Autodesk Fusion 360 part; units mm, degrees
(part 2 of 2)
  constraint tangent L75 A74
  constraint tangent L75 A75
  constraint tangent L72 A75
  constraint tangent L76 A76
  constraint tangent L77 A76
  constraint tangent L77 A77
  constraint tangent L78 A77
  constraint tangent L78 A78
  constraint tangent L79 A78
  constraint tangent L79 A79
  constraint tangent L76 A79
  constraint tangent L80 A80
  constraint tangent L81 A80
  constraint tangent L81 A81
  constraint tangent L82 A81
  constraint tangent L82 A82
  constraint tangent L83 A82
  constraint tangent L83 A83
  constraint tangent L80 A83
  constraint tangent L84 A84
  constraint tangent L85 A84
  constraint tangent L85 A85
  constraint tangent L86 A85
  constraint tangent L86 A86
  constraint tangent L87 A86
  constraint tangent L87 A87
  constraint tangent L84 A87
  constraint tangent L88 A88
  constraint tangent L89 A88
  constraint tangent L89 A89
  constraint tangent L90 A89
  constraint tangent L90 A90
  constraint tangent L91 A90
  constraint tangent L91 A91
  constraint tangent L88 A91
  constraint tangent L92 A92
  constraint tangent L93 A92
  constraint tangent L93 A93
  constraint tangent L94 A93
  constraint tangent L94 A94
  constraint tangent L95 A94
  constraint tangent L95 A95
  constraint tangent L92 A95
  constraint tangent L96 A96
  constraint tangent L97 A96
  constraint tangent L97 A97
  constraint tangent L98 A97
  constraint tangent L98 A98
  constraint tangent L99 A98
  constraint tangent L99 A99
  constraint tangent L96 A99
  constraint tangent L100 A100
  constraint tangent L101 A100
  constraint tangent L101 A101
  constraint tangent L102 A101
  constraint tangent L102 A102
  constraint tangent L103 A102
  constraint tangent L103 A103
  constraint tangent L100 A103
  constraint tangent L104 A104
  constraint tangent L105 A104
  constraint tangent L105 A105
  constraint tangent L106 A105
  constraint tangent L106 A106
  constraint tangent L107 A106
  constraint tangent L107 A107
  constraint tangent L104 A107
  constraint tangent L108 A108
  constraint tangent L109 A108
  constraint tangent L109 A109
  constraint tangent L110 A109
  constraint tangent L110 A110
  constraint tangent L111 A110
  constraint tangent L111 A111
  constraint tangent L108 A111
  constraint tangent L112 A112
  constraint tangent L113 A112
  constraint tangent L113 A113
  constraint tangent L114 A113
  constraint tangent L114 A114
  constraint tangent L115 A114
  constraint tangent L115 A115
  constraint tangent L112 A115
  constraint tangent L116 A116
  constraint tangent L117 A116
  constraint tangent L117 A117
  constraint tangent L118 A117
  constraint tangent L118 A118
  constraint tangent L119 A118
  constraint tangent L119 A119
  constraint tangent L116 A119
  constraint tangent L120 A120
  constraint tangent L121 A120
  constraint tangent L121 A121
  constraint tangent L122 A121
  constraint tangent L122 A122
  constraint tangent L123 A122
  constraint tangent L123 A123
  constraint tangent L120 A123
  constraint tangent L124 A124
  constraint tangent L125 A124
  constraint tangent L125 A125
  constraint tangent L126 A125
  constraint tangent L126 A126
  constraint tangent L127 A126
  constraint tangent L127 A127
  constraint tangent L124 A127
  constraint tangent L128 A128
  constraint tangent L129 A128
  constraint tangent L129 A129
  constraint tangent L130 A129
  constraint tangent L130 A130
  constraint tangent L131 A130
  constraint tangent L131 A131
  constraint tangent L128 A131
  constraint tangent L132 A132
  constraint tangent L133 A132
  constraint tangent L133 A133
  constraint tangent L134 A133
  constraint tangent L134 A134
  constraint tangent L135 A134
  constraint tangent L135 A135
  constraint tangent L132 A135
  constraint tangent L136 A136
  constraint tangent L137 A136
  constraint tangent L137 A137
  constraint tangent L138 A137
  constraint tangent L138 A138
  constraint tangent L139 A138
  constraint tangent L139 A139
  constraint tangent L136 A139
  constraint tangent L140 A140
  constraint tangent L141 A140
  constraint tangent L141 A141
  constraint tangent L142 A141
  constraint tangent L142 A142
  constraint tangent L143 A142
  constraint tangent L143 A143
  constraint tangent L140 A143
extrude "Right recessed grille" cut sketch "Esboço41" along normal blind 1.55 bodies 1
ref_plane "Plano de trabalho26" through (-27, 0, 0) normal (1, 0, 0) x (0, 1, 0)
sketch "Esboço42" plane through (-27, 0, 0) normal (1, 0, 0) x (0, 0, -1)
  line L0 (49.75, 12) -> (52.25, 12)
  line L1 (52.5, 12.25) -> (52.5, 12.55)
  line L2 (52.25, 12.8) -> (49.75, 12.8)
  line L3 (49.5, 12.55) -> (49.5, 12.25)
  arc A0 (52.25, 12) -> (52.5, 12.25) centre (52.25, 12.25) ccw
  arc A1 (52.5, 12.55) -> (52.25, 12.8) centre (52.25, 12.55) ccw
  arc A2 (49.75, 12.8) -> (49.5, 12.55) centre (49.75, 12.55) ccw
  arc A3 (49.5, 12.25) -> (49.75, 12) centre (49.75, 12.25) ccw
  line L4 (45.35, 12) -> (47.85, 12)
  line L5 (48.1, 12.25) -> (48.1, 12.55)
  line L6 (47.85, 12.8) -> (45.35, 12.8)
  line L7 (45.1, 12.55) -> (45.1, 12.25)
  arc A4 (47.85, 12) -> (48.1, 12.25) centre (47.85, 12.25) ccw
  arc A5 (48.1, 12.55) -> (47.85, 12.8) centre (47.85, 12.55) ccw
  arc A6 (45.35, 12.8) -> (45.1, 12.55) centre (45.35, 12.55) ccw
  arc A7 (45.1, 12.25) -> (45.35, 12) centre (45.35, 12.25) ccw
  line L8 (40.95, 12) -> (43.45, 12)
  line L9 (43.7, 12.25) -> (43.7, 12.55)
  line L10 (43.45, 12.8) -> (40.95, 12.8)
  line L11 (40.7, 12.55) -> (40.7, 12.25)
  arc A8 (43.45, 12) -> (43.7, 12.25) centre (43.45, 12.25) ccw
  arc A9 (43.7, 12.55) -> (43.45, 12.8) centre (43.45, 12.55) ccw
  arc A10 (40.95, 12.8) -> (40.7, 12.55) centre (40.95, 12.55) ccw
  arc A11 (40.7, 12.25) -> (40.95, 12) centre (40.95, 12.25) ccw
  line L12 (36.55, 12) -> (39.05, 12)
  line L13 (39.3, 12.25) -> (39.3, 12.55)
  line L14 (39.05, 12.8) -> (36.55, 12.8)
  line L15 (36.3, 12.55) -> (36.3, 12.25)
  arc A12 (39.05, 12) -> (39.3, 12.25) centre (39.05, 12.25) ccw
  arc A13 (39.3, 12.55) -> (39.05, 12.8) centre (39.05, 12.55) ccw
  arc A14 (36.55, 12.8) -> (36.3, 12.55) centre (36.55, 12.55) ccw
  arc A15 (36.3, 12.25) -> (36.55, 12) centre (36.55, 12.25) ccw
  line L16 (32.15, 12) -> (34.65, 12)
  line L17 (34.9, 12.25) -> (34.9, 12.55)
  line L18 (34.65, 12.8) -> (32.15, 12.8)
  line L19 (31.9, 12.55) -> (31.9, 12.25)
  arc A16 (34.65, 12) -> (34.9, 12.25) centre (34.65, 12.25) ccw
  arc A17 (34.9, 12.55) -> (34.65, 12.8) centre (34.65, 12.55) ccw
  arc A18 (32.15, 12.8) -> (31.9, 12.55) centre (32.15, 12.55) ccw
  arc A19 (31.9, 12.25) -> (32.15, 12) centre (32.15, 12.25) ccw
  line L20 (27.75, 12) -> (30.25, 12)
  line L21 (30.5, 12.25) -> (30.5, 12.55)
  line L22 (30.25, 12.8) -> (27.75, 12.8)
  line L23 (27.5, 12.55) -> (27.5, 12.25)
  arc A20 (30.25, 12) -> (30.5, 12.25) centre (30.25, 12.25) ccw
  arc A21 (30.5, 12.55) -> (30.25, 12.8) centre (30.25, 12.55) ccw
  arc A22 (27.75, 12.8) -> (27.5, 12.55) centre (27.75, 12.55) ccw
  arc A23 (27.5, 12.25) -> (27.75, 12) centre (27.75, 12.25) ccw
  line L24 (23.35, 12) -> (25.85, 12)
  line L25 (26.1, 12.25) -> (26.1, 12.55)
  line L26 (25.85, 12.8) -> (23.35, 12.8)
  line L27 (23.1, 12.55) -> (23.1, 12.25)
  arc A24 (25.85, 12) -> (26.1, 12.25) centre (25.85, 12.25) ccw
  arc A25 (26.1, 12.55) -> (25.85, 12.8) centre (25.85, 12.55) ccw
  arc A26 (23.35, 12.8) -> (23.1, 12.55) centre (23.35, 12.55) ccw
  arc A27 (23.1, 12.25) -> (23.35, 12) centre (23.35, 12.25) ccw
  line L28 (18.95, 12) -> (21.45, 12)
  line L29 (21.7, 12.25) -> (21.7, 12.55)
  line L30 (21.45, 12.8) -> (18.95, 12.8)
  line L31 (18.7, 12.55) -> (18.7, 12.25)
  arc A28 (21.45, 12) -> (21.7, 12.25) centre (21.45, 12.25) ccw
  arc A29 (21.7, 12.55) -> (21.45, 12.8) centre (21.45, 12.55) ccw
  arc A30 (18.95, 12.8) -> (18.7, 12.55) centre (18.95, 12.55) ccw
  arc A31 (18.7, 12.25) -> (18.95, 12) centre (18.95, 12.25) ccw
  line L32 (14.55, 12) -> (17.05, 12)
  line L33 (17.3, 12.25) -> (17.3, 12.55)
  line L34 (17.05, 12.8) -> (14.55, 12.8)
  line L35 (14.3, 12.55) -> (14.3, 12.25)
  arc A32 (17.05, 12) -> (17.3, 12.25) centre (17.05, 12.25) ccw
  arc A33 (17.3, 12.55) -> (17.05, 12.8) centre (17.05, 12.55) ccw
  arc A34 (14.55, 12.8) -> (14.3, 12.55) centre (14.55, 12.55) ccw
  arc A35 (14.3, 12.25) -> (14.55, 12) centre (14.55, 12.25) ccw
  line L36 (49.75, 13.8) -> (52.25, 13.8)
  line L37 (52.5, 14.05) -> (52.5, 14.35)
  line L38 (52.25, 14.6) -> (49.75, 14.6)
  line L39 (49.5, 14.35) -> (49.5, 14.05)
  arc A36 (52.25, 13.8) -> (52.5, 14.05) centre (52.25, 14.05) ccw
  arc A37 (52.5, 14.35) -> (52.25, 14.6) centre (52.25, 14.35) ccw
  arc A38 (49.75, 14.6) -> (49.5, 14.35) centre (49.75, 14.35) ccw
  arc A39 (49.5, 14.05) -> (49.75, 13.8) centre (49.75, 14.05) ccw
  line L40 (45.35, 13.8) -> (47.85, 13.8)
  line L41 (48.1, 14.05) -> (48.1, 14.35)
  line L42 (47.85, 14.6) -> (45.35, 14.6)
  line L43 (45.1, 14.35) -> (45.1, 14.05)
  arc A40 (47.85, 13.8) -> (48.1, 14.05) centre (47.85, 14.05) ccw
  arc A41 (48.1, 14.35) -> (47.85, 14.6) centre (47.85, 14.35) ccw
  arc A42 (45.35, 14.6) -> (45.1, 14.35) centre (45.35, 14.35) ccw
  arc A43 (45.1, 14.05) -> (45.35, 13.8) centre (45.35, 14.05) ccw
  line L44 (40.95, 13.8) -> (43.45, 13.8)
  line L45 (43.7, 14.05) -> (43.7, 14.35)
  line L46 (43.45, 14.6) -> (40.95, 14.6)
  line L47 (40.7, 14.35) -> (40.7, 14.05)
  arc A44 (43.45, 13.8) -> (43.7, 14.05) centre (43.45, 14.05) ccw
  arc A45 (43.7, 14.35) -> (43.45, 14.6) centre (43.45, 14.35) ccw
  arc A46 (40.95, 14.6) -> (40.7, 14.35) centre (40.95, 14.35) ccw
  arc A47 (40.7, 14.05) -> (40.95, 13.8) centre (40.95, 14.05) ccw
  line L48 (36.55, 13.8) -> (39.05, 13.8)
  line L49 (39.3, 14.05) -> (39.3, 14.35)
  line L50 (39.05, 14.6) -> (36.55, 14.6)
  line L51 (36.3, 14.35) -> (36.3, 14.05)
  arc A48 (39.05, 13.8) -> (39.3, 14.05) centre (39.05, 14.05) ccw
  arc A49 (39.3, 14.35) -> (39.05, 14.6) centre (39.05, 14.35) ccw
  arc A50 (36.55, 14.6) -> (36.3, 14.35) centre (36.55, 14.35) ccw
  arc A51 (36.3, 14.05) -> (36.55, 13.8) centre (36.55, 14.05) ccw
  line L52 (32.15, 13.8) -> (34.65, 13.8)
  line L53 (34.9, 14.05) -> (34.9, 14.35)
  line L54 (34.65, 14.6) -> (32.15, 14.6)
  line L55 (31.9, 14.35) -> (31.9, 14.05)
  arc A52 (34.65, 13.8) -> (34.9, 14.05) centre (34.65, 14.05) ccw
  arc A53 (34.9, 14.35) -> (34.65, 14.6) centre (34.65, 14.35) ccw
  arc A54 (32.15, 14.6) -> (31.9, 14.35) centre (32.15, 14.35) ccw
  arc A55 (31.9, 14.05) -> (32.15, 13.8) centre (32.15, 14.05) ccw
  line L56 (27.75, 13.8) -> (30.25, 13.8)
  line L57 (30.5, 14.05) -> (30.5, 14.35)
  line L58 (30.25, 14.6) -> (27.75, 14.6)
  line L59 (27.5, 14.35) -> (27.5, 14.05)
  arc A56 (30.25, 13.8) -> (30.5, 14.05) centre (30.25, 14.05) ccw
  arc A57 (30.5, 14.35) -> (30.25, 14.6) centre (30.25, 14.35) ccw
  arc A58 (27.75, 14.6) -> (27.5, 14.35) centre (27.75, 14.35) ccw
  arc A59 (27.5, 14.05) -> (27.75, 13.8) centre (27.75, 14.05) ccw
  line L60 (23.35, 13.8) -> (25.85, 13.8)
  line L61 (26.1, 14.05) -> (26.1, 14.35)
  line L62 (25.85, 14.6) -> (23.35, 14.6)
  line L63 (23.1, 14.35) -> (23.1, 14.05)
  arc A60 (25.85, 13.8) -> (26.1, 14.05) centre (25.85, 14.05) ccw
  arc A61 (26.1, 14.35) -> (25.85, 14.6) centre (25.85, 14.35) ccw
  arc A62 (23.35, 14.6) -> (23.1, 14.35) centre (23.35, 14.35) ccw
  arc A63 (23.1, 14.05) -> (23.35, 13.8) centre (23.35, 14.05) ccw
  line L64 (18.95, 13.8) -> (21.45, 13.8)
  line L65 (21.7, 14.05) -> (21.7, 14.35)
  line L66 (21.45, 14.6) -> (18.95, 14.6)
  line L67 (18.7, 14.35) -> (18.7, 14.05)
  arc A64 (21.45, 13.8) -> (21.7, 14.05) centre (21.45, 14.05) ccw
  arc A65 (21.7, 14.35) -> (21.45, 14.6) centre (21.45, 14.35) ccw
  arc A66 (18.95, 14.6) -> (18.7, 14.35) centre (18.95, 14.35) ccw
  arc A67 (18.7, 14.05) -> (18.95, 13.8) centre (18.95, 14.05) ccw
  line L68 (14.55, 13.8) -> (17.05, 13.8)
  line L69 (17.3, 14.05) -> (17.3, 14.35)
  line L70 (17.05, 14.6) -> (14.55, 14.6)
  line L71 (14.3, 14.35) -> (14.3, 14.05)
  arc A68 (17.05, 13.8) -> (17.3, 14.05) centre (17.05, 14.05) ccw
  arc A69 (17.3, 14.35) -> (17.05, 14.6) centre (17.05, 14.35) ccw
  arc A70 (14.55, 14.6) -> (14.3, 14.35) centre (14.55, 14.35) ccw
  arc A71 (14.3, 14.05) -> (14.55, 13.8) centre (14.55, 14.05) ccw
  line L72 (49.75, 15.6) -> (52.25, 15.6)
  line L73 (52.5, 15.85) -> (52.5, 16.15)
  line L74 (52.25, 16.4) -> (49.75, 16.4)
  line L75 (49.5, 16.15) -> (49.5, 15.85)
  arc A72 (52.25, 15.6) -> (52.5, 15.85) centre (52.25, 15.85) ccw
  arc A73 (52.5, 16.15) -> (52.25, 16.4) centre (52.25, 16.15) ccw
  arc A74 (49.75, 16.4) -> (49.5, 16.15) centre (49.75, 16.15) ccw
  arc A75 (49.5, 15.85) -> (49.75, 15.6) centre (49.75, 15.85) ccw
  line L76 (45.35, 15.6) -> (47.85, 15.6)
  line L77 (48.1, 15.85) -> (48.1, 16.15)
  line L78 (47.85, 16.4) -> (45.35, 16.4)
  line L79 (45.1, 16.15) -> (45.1, 15.85)
  arc A76 (47.85, 15.6) -> (48.1, 15.85) centre (47.85, 15.85) ccw
  arc A77 (48.1, 16.15) -> (47.85, 16.4) centre (47.85, 16.15) ccw
  arc A78 (45.35, 16.4) -> (45.1, 16.15) centre (45.35, 16.15) ccw
  arc A79 (45.1, 15.85) -> (45.35, 15.6) centre (45.35, 15.85) ccw
  line L80 (40.95, 15.6) -> (43.45, 15.6)
  line L81 (43.7, 15.85) -> (43.7, 16.15)
  line L82 (43.45, 16.4) -> (40.95, 16.4)
  line L83 (40.7, 16.15) -> (40.7, 15.85)
  arc A80 (43.45, 15.6) -> (43.7, 15.85) centre (43.45, 15.85) ccw
  arc A81 (43.7, 16.15) -> (43.45, 16.4) centre (43.45, 16.15) ccw
  arc A82 (40.95, 16.4) -> (40.7, 16.15) centre (40.95, 16.15) ccw
  arc A83 (40.7, 15.85) -> (40.95, 15.6) centre (40.95, 15.85) ccw
  line L84 (36.55, 15.6) -> (39.05, 15.6)
  line L85 (39.3, 15.85) -> (39.3, 16.15)
  line L86 (39.05, 16.4) -> (36.55, 16.4)
  line L87 (36.3, 16.15) -> (36.3, 15.85)
  arc A84 (39.05, 15.6) -> (39.3, 15.85) centre (39.05, 15.85) ccw
  arc A85 (39.3, 16.15) -> (39.05, 16.4) centre (39.05, 16.15) ccw
  arc A86 (36.55, 16.4) -> (36.3, 16.15) centre (36.55, 16.15) ccw
  arc A87 (36.3, 15.85) -> (36.55, 15.6) centre (36.55, 15.85) ccw
  line L88 (32.15, 15.6) -> (34.65, 15.6)
  line L89 (34.9, 15.85) -> (34.9, 16.15)
  line L90 (34.65, 16.4) -> (32.15, 16.4)
  line L91 (31.9, 16.15) -> (31.9, 15.85)
  arc A88 (34.65, 15.6) -> (34.9, 15.85) centre (34.65, 15.85) ccw
  arc A89 (34.9, 16.15) -> (34.65, 16.4) centre (34.65, 16.15) ccw
  arc A90 (32.15, 16.4) -> (31.9, 16.15) centre (32.15, 16.15) ccw
  arc A91 (31.9, 15.85) -> (32.15, 15.6) centre (32.15, 15.85) ccw
  line L92 (27.75, 15.6) -> (30.25, 15.6)
  line L93 (30.5, 15.85) -> (30.5, 16.15)
  line L94 (30.25, 16.4) -> (27.75, 16.4)
  line L95 (27.5, 16.15) -> (27.5, 15.85)
  arc A92 (30.25, 15.6) -> (30.5, 15.85) centre (30.25, 15.85) ccw
  arc A93 (30.5, 16.15) -> (30.25, 16.4) centre (30.25, 16.15) ccw
  arc A94 (27.75, 16.4) -> (27.5, 16.15) centre (27.75, 16.15) ccw
  arc A95 (27.5, 15.85) -> (27.75, 15.6) centre (27.75, 15.85) ccw
  line L96 (23.35, 15.6) -> (25.85, 15.6)
  line L97 (26.1, 15.85) -> (26.1, 16.15)
  line L98 (25.85, 16.4) -> (23.35, 16.4)
  line L99 (23.1, 16.15) -> (23.1, 15.85)
  arc A96 (25.85, 15.6) -> (26.1, 15.85) centre (25.85, 15.85) ccw
  arc A97 (26.1, 16.15) -> (25.85, 16.4) centre (25.85, 16.15) ccw
  arc A98 (23.35, 16.4) -> (23.1, 16.15) centre (23.35, 16.15) ccw
  arc A99 (23.1, 15.85) -> (23.35, 15.6) centre (23.35, 15.85) ccw
  line L100 (18.95, 15.6) -> (21.45, 15.6)
  line L101 (21.7, 15.85) -> (21.7, 16.15)
  line L102 (21.45, 16.4) -> (18.95, 16.4)
  line L103 (18.7, 16.15) -> (18.7, 15.85)
  arc A100 (21.45, 15.6) -> (21.7, 15.85) centre (21.45, 15.85) ccw
  arc A101 (21.7, 16.15) -> (21.45, 16.4) centre (21.45, 16.15) ccw
  arc A102 (18.95, 16.4) -> (18.7, 16.15) centre (18.95, 16.15) ccw
  arc A103 (18.7, 15.85) -> (18.95, 15.6) centre (18.95, 15.85) ccw
  line L104 (14.55, 15.6) -> (17.05, 15.6)
  line L105 (17.3, 15.85) -> (17.3, 16.15)
  line L106 (17.05, 16.4) -> (14.55, 16.4)
  line L107 (14.3, 16.15) -> (14.3, 15.85)
  arc A104 (17.05, 15.6) -> (17.3, 15.85) centre (17.05, 15.85) ccw
  arc A105 (17.3, 16.15) -> (17.05, 16.4) centre (17.05, 16.15) ccw
  arc A106 (14.55, 16.4) -> (14.3, 16.15) centre (14.55, 16.15) ccw
  arc A107 (14.3, 15.85) -> (14.55, 15.6) centre (14.55, 15.85) ccw
  line L108 (49.75, 17.4) -> (52.25, 17.4)
  line L109 (52.5, 17.65) -> (52.5, 17.95)
  line L110 (52.25, 18.2) -> (49.75, 18.2)
  line L111 (49.5, 17.95) -> (49.5, 17.65)
  arc A108 (52.25, 17.4) -> (52.5, 17.65) centre (52.25, 17.65) ccw
  arc A109 (52.5, 17.95) -> (52.25, 18.2) centre (52.25, 17.95) ccw
  arc A110 (49.75, 18.2) -> (49.5, 17.95) centre (49.75, 17.95) ccw
  arc A111 (49.5, 17.65) -> (49.75, 17.4) centre (49.75, 17.65) ccw
  line L112 (45.35, 17.4) -> (47.85, 17.4)
  line L113 (48.1, 17.65) -> (48.1, 17.95)
  line L114 (47.85, 18.2) -> (45.35, 18.2)
  line L115 (45.1, 17.95) -> (45.1, 17.65)
  arc A112 (47.85, 17.4) -> (48.1, 17.65) centre (47.85, 17.65) ccw
  arc A113 (48.1, 17.95) -> (47.85, 18.2) centre (47.85, 17.95) ccw
  arc A114 (45.35, 18.2) -> (45.1, 17.95) centre (45.35, 17.95) ccw
  arc A115 (45.1, 17.65) -> (45.35, 17.4) centre (45.35, 17.65) ccw
  line L116 (40.95, 17.4) -> (43.45, 17.4)
  line L117 (43.7, 17.65) -> (43.7, 17.95)
  line L118 (43.45, 18.2) -> (40.95, 18.2)
  line L119 (40.7, 17.95) -> (40.7, 17.65)
  arc A116 (43.45, 17.4) -> (43.7, 17.65) centre (43.45, 17.65) ccw
  arc A117 (43.7, 17.95) -> (43.45, 18.2) centre (43.45, 17.95) ccw
  arc A118 (40.95, 18.2) -> (40.7, 17.95) centre (40.95, 17.95) ccw
  arc A119 (40.7, 17.65) -> (40.95, 17.4) centre (40.95, 17.65) ccw
  line L120 (36.55, 17.4) -> (39.05, 17.4)
  line L121 (39.3, 17.65) -> (39.3, 17.95)
  line L122 (39.05, 18.2) -> (36.55, 18.2)
  line L123 (36.3, 17.95) -> (36.3, 17.65)
  arc A120 (39.05, 17.4) -> (39.3, 17.65) centre (39.05, 17.65) ccw
  arc A121 (39.3, 17.95) -> (39.05, 18.2) centre (39.05, 17.95) ccw
  arc A122 (36.55, 18.2) -> (36.3, 17.95) centre (36.55, 17.95) ccw
  arc A123 (36.3, 17.65) -> (36.55, 17.4) centre (36.55, 17.65) ccw
  line L124 (32.15, 17.4) -> (34.65, 17.4)
  line L125 (34.9, 17.65) -> (34.9, 17.95)
  line L126 (34.65, 18.2) -> (32.15, 18.2)
  line L127 (31.9, 17.95) -> (31.9, 17.65)
  arc A124 (34.65, 17.4) -> (34.9, 17.65) centre (34.65, 17.65) ccw
  arc A125 (34.9, 17.95) -> (34.65, 18.2) centre (34.65, 17.95) ccw
  arc A126 (32.15, 18.2) -> (31.9, 17.95) centre (32.15, 17.95) ccw
  arc A127 (31.9, 17.65) -> (32.15, 17.4) centre (32.15, 17.65) ccw
  line L128 (27.75, 17.4) -> (30.25, 17.4)
  line L129 (30.5, 17.65) -> (30.5, 17.95)
  line L130 (30.25, 18.2) -> (27.75, 18.2)
  line L131 (27.5, 17.95) -> (27.5, 17.65)
  arc A128 (30.25, 17.4) -> (30.5, 17.65) centre (30.25, 17.65) ccw
  arc A129 (30.5, 17.95) -> (30.25, 18.2) centre (30.25, 17.95) ccw
  arc A130 (27.75, 18.2) -> (27.5, 17.95) centre (27.75, 17.95) ccw
  arc A131 (27.5, 17.65) -> (27.75, 17.4) centre (27.75, 17.65) ccw
  line L132 (23.35, 17.4) -> (25.85, 17.4)
  line L133 (26.1, 17.65) -> (26.1, 17.95)
  line L134 (25.85, 18.2) -> (23.35, 18.2)
  line L135 (23.1, 17.95) -> (23.1, 17.65)
  arc A132 (25.85, 17.4) -> (26.1, 17.65) centre (25.85, 17.65) ccw
  arc A133 (26.1, 17.95) -> (25.85, 18.2) centre (25.85, 17.95) ccw
  arc A134 (23.35, 18.2) -> (23.1, 17.95) centre (23.35, 17.95) ccw
  arc A135 (23.1, 17.65) -> (23.35, 17.4) centre (23.35, 17.65) ccw
  line L136 (18.95, 17.4) -> (21.45, 17.4)
  line L137 (21.7, 17.65) -> (21.7, 17.95)
  line L138 (21.45, 18.2) -> (18.95, 18.2)
  line L139 (18.7, 17.95) -> (18.7, 17.65)
  arc A136 (21.45, 17.4) -> (21.7, 17.65) centre (21.45, 17.65) ccw
  arc A137 (21.7, 17.95) -> (21.45, 18.2) centre (21.45, 17.95) ccw
  arc A138 (18.95, 18.2) -> (18.7, 17.95) centre (18.95, 17.95) ccw
  arc A139 (18.7, 17.65) -> (18.95, 17.4) centre (18.95, 17.65) ccw
  line L140 (14.55, 17.4) -> (17.05, 17.4)
  line L141 (17.3, 17.65) -> (17.3, 17.95)
  line L142 (17.05, 18.2) -> (14.55, 18.2)
  line L143 (14.3, 17.95) -> (14.3, 17.65)
  arc A140 (17.05, 17.4) -> (17.3, 17.65) centre (17.05, 17.65) ccw
  arc A141 (17.3, 17.95) -> (17.05, 18.2) centre (17.05, 17.95) ccw
  arc A142 (14.55, 18.2) -> (14.3, 17.95) centre (14.55, 17.95) ccw
  arc A143 (14.3, 17.65) -> (14.55, 17.4) centre (14.55, 17.65) ccw
  constraint tangent L0 A0
  constraint tangent L1 A0
  constraint tangent L1 A1
  constraint tangent L2 A1
  constraint tangent L2 A2
  constraint tangent L3 A2
  constraint tangent L3 A3
  constraint tangent L0 A3
  constraint tangent L4 A4
  constraint tangent L5 A4
  constraint tangent L5 A5
  constraint tangent L6 A5
  constraint tangent L6 A6
  constraint tangent L7 A6
  constraint tangent L7 A7
  constraint tangent L4 A7
  constraint tangent L8 A8
  constraint tangent L9 A8
  constraint tangent L9 A9
  constraint tangent L10 A9
  constraint tangent L10 A10
  constraint tangent L11 A10
  constraint tangent L11 A11
  constraint tangent L8 A11
  constraint tangent L12 A12
  constraint tangent L13 A12
  constraint tangent L13 A13
  constraint tangent L14 A13
  constraint tangent L14 A14
  constraint tangent L15 A14
  constraint tangent L15 A15
  constraint tangent L12 A15
  constraint tangent L16 A16
  constraint tangent L17 A16
  constraint tangent L17 A17
  constraint tangent L18 A17
  constraint tangent L18 A18
  constraint tangent L19 A18
  constraint tangent L19 A19
  constraint tangent L16 A19
  constraint tangent L20 A20
  constraint tangent L21 A20
  constraint tangent L21 A21
  constraint tangent L22 A21
  constraint tangent L22 A22
  constraint tangent L23 A22
  constraint tangent L23 A23
  constraint tangent L20 A23
  constraint tangent L24 A24
  constraint tangent L25 A24
  constraint tangent L25 A25
  constraint tangent L26 A25
  constraint tangent L26 A26
  constraint tangent L27 A26
  constraint tangent L27 A27
  constraint tangent L24 A27
  constraint tangent L28 A28
  constraint tangent L29 A28
  constraint tangent L29 A29
  constraint tangent L30 A29
  constraint tangent L30 A30
  constraint tangent L31 A30
  constraint tangent L31 A31
  constraint tangent L28 A31
  constraint tangent L32 A32
  constraint tangent L33 A32
  constraint tangent L33 A33
  constraint tangent L34 A33
  constraint tangent L34 A34
  constraint tangent L35 A34
  constraint tangent L35 A35
  constraint tangent L32 A35
  constraint tangent L36 A36
  constraint tangent L37 A36
  constraint tangent L37 A37
  constraint tangent L38 A37
  constraint tangent L38 A38
  constraint tangent L39 A38
  constraint tangent L39 A39
  constraint tangent L36 A39
  constraint tangent L40 A40
  constraint tangent L41 A40
  constraint tangent L41 A41
  constraint tangent L42 A41
  constraint tangent L42 A42
  constraint tangent L43 A42
  constraint tangent L43 A43
  constraint tangent L40 A43
  constraint tangent L44 A44
  constraint tangent L45 A44
  constraint tangent L45 A45
  constraint tangent L46 A45
  constraint tangent L46 A46
  constraint tangent L47 A46
  constraint tangent L47 A47
  constraint tangent L44 A47
  constraint tangent L48 A48
  constraint tangent L49 A48
  constraint tangent L49 A49
  constraint tangent L50 A49
  constraint tangent L50 A50
  constraint tangent L51 A50
  constraint tangent L51 A51
  constraint tangent L48 A51
  constraint tangent L52 A52
  constraint tangent L53 A52
  constraint tangent L53 A53
  constraint tangent L54 A53
  constraint tangent L54 A54
  constraint tangent L55 A54
  constraint tangent L55 A55
  constraint tangent L52 A55
  constraint tangent L56 A56
  constraint tangent L57 A56
  constraint tangent L57 A57
  constraint tangent L58 A57
  constraint tangent L58 A58
  constraint tangent L59 A58
  constraint tangent L59 A59
  constraint tangent L56 A59
  constraint tangent L60 A60
  constraint tangent L61 A60
  constraint tangent L61 A61
  constraint tangent L62 A61
  constraint tangent L62 A62
  constraint tangent L63 A62
  constraint tangent L63 A63
  constraint tangent L60 A63
  constraint tangent L64 A64
  constraint tangent L65 A64
  constraint tangent L65 A65
  constraint tangent L66 A65
  constraint tangent L66 A66
  constraint tangent L67 A66
  constraint tangent L67 A67
  constraint tangent L64 A67
  constraint tangent L68 A68
  constraint tangent L69 A68
  constraint tangent L69 A69
  constraint tangent L70 A69
  constraint tangent L70 A70
  constraint tangent L71 A70
  constraint tangent L71 A71
  constraint tangent L68 A71
  constraint tangent L72 A72
  constraint tangent L73 A72
  constraint tangent L73 A73
  constraint tangent L74 A73
  constraint tangent L74 A74
  constraint tangent L75 A74
  constraint tangent L75 A75
  constraint tangent L72 A75
  constraint tangent L76 A76
  constraint tangent L77 A76
  constraint tangent L77 A77
  constraint tangent L78 A77
  constraint tangent L78 A78
  constraint tangent L79 A78
  constraint tangent L79 A79
  constraint tangent L76 A79
  constraint tangent L80 A80
  constraint tangent L81 A80
  constraint tangent L81 A81
  constraint tangent L82 A81
  constraint tangent L82 A82
  constraint tangent L83 A82
  constraint tangent L83 A83
  constraint tangent L80 A83
  constraint tangent L84 A84
  constraint tangent L85 A84
  constraint tangent L85 A85
  constraint tangent L86 A85
  constraint tangent L86 A86
  constraint tangent L87 A86
  constraint tangent L87 A87
  constraint tangent L84 A87
  constraint tangent L88 A88
  constraint tangent L89 A88
  constraint tangent L89 A89
  constraint tangent L90 A89
  constraint tangent L90 A90
  constraint tangent L91 A90
  constraint tangent L91 A91
  constraint tangent L88 A91
  constraint tangent L92 A92
  constraint tangent L93 A92
  constraint tangent L93 A93
  constraint tangent L94 A93
  constraint tangent L94 A94
  constraint tangent L95 A94
  constraint tangent L95 A95
  constraint tangent L92 A95
  constraint tangent L96 A96
  constraint tangent L97 A96
  constraint tangent L97 A97
  constraint tangent L98 A97
  constraint tangent L98 A98
  constraint tangent L99 A98
  constraint tangent L99 A99
  constraint tangent L96 A99
  constraint tangent L100 A100
  constraint tangent L101 A100
  constraint tangent L101 A101
  constraint tangent L102 A101
  constraint tangent L102 A102
  constraint tangent L103 A102
  constraint tangent L103 A103
  constraint tangent L100 A103
  constraint tangent L104 A104
  constraint tangent L105 A104
  constraint tangent L105 A105
  constraint tangent L106 A105
  constraint tangent L106 A106
  constraint tangent L107 A106
  constraint tangent L107 A107
  constraint tangent L104 A107
  constraint tangent L108 A108
  constraint tangent L109 A108
  constraint tangent L109 A109
  constraint tangent L110 A109
  constraint tangent L110 A110
  constraint tangent L111 A110
  constraint tangent L111 A111
  constraint tangent L108 A111
  constraint tangent L112 A112
  constraint tangent L113 A112
  constraint tangent L113 A113
  constraint tangent L114 A113
  constraint tangent L114 A114
  constraint tangent L115 A114
  constraint tangent L115 A115
  constraint tangent L112 A115
  constraint tangent L116 A116
  constraint tangent L117 A116
  constraint tangent L117 A117
  constraint tangent L118 A117
  constraint tangent L118 A118
  constraint tangent L119 A118
  constraint tangent L119 A119
  constraint tangent L116 A119
  constraint tangent L120 A120
  constraint tangent L121 A120
  constraint tangent L121 A121
  constraint tangent L122 A121
  constraint tangent L122 A122
  constraint tangent L123 A122
  constraint tangent L123 A123
  constraint tangent L120 A123
  constraint tangent L124 A124
  constraint tangent L125 A124
  constraint tangent L125 A125
  constraint tangent L126 A125
  constraint tangent L126 A126
  constraint tangent L127 A126
  constraint tangent L127 A127
  constraint tangent L124 A127
  constraint tangent L128 A128
  constraint tangent L129 A128
  constraint tangent L129 A129
  constraint tangent L130 A129
  constraint tangent L130 A130
  constraint tangent L131 A130
  constraint tangent L131 A131
  constraint tangent L128 A131
  constraint tangent L132 A132
  constraint tangent L133 A132
  constraint tangent L133 A133
  constraint tangent L134 A133
  constraint tangent L134 A134
  constraint tangent L135 A134
  constraint tangent L135 A135
  constraint tangent L132 A135
  constraint tangent L136 A136
  constraint tangent L137 A136
  constraint tangent L137 A137
  constraint tangent L138 A137
  constraint tangent L138 A138
  constraint tangent L139 A138
  constraint tangent L139 A139
  constraint tangent L136 A139
  constraint tangent L140 A140
  constraint tangent L141 A140
  constraint tangent L141 A141
  constraint tangent L142 A141
  constraint tangent L142 A142
  constraint tangent L143 A142
  constraint tangent L143 A143
  constraint tangent L140 A143
extrude "Left recessed grille" cut sketch "Esboço42" along normal blind 1.55 bodies 1
hidden bodies 4
named bodies: "stand_v3_body", "stand_v3_base", "mock_display", "mock_esp"
